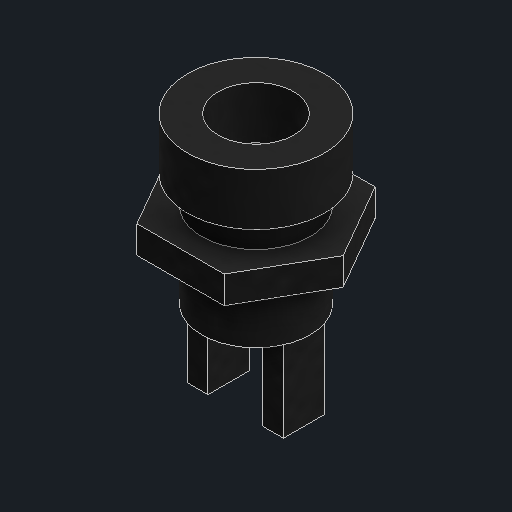
# Autodesk Inventor part: dc_socket_5.5x2.1_M8
Saved by Autodesk Inventor 2027.1 (Build 311270010, 270A)
## iProperties
Created: 2026-10-29
Part Number: dc_socket_5.5x2.1_M8
Material: Generic
Document SubType Name: Modeling
Designer: alexg
Density: 1 g/cm^3
Appearance: Black
Author: alexg
Autodesk Inventor part; units mm, degrees
sketch "Flange sketch" plane through (0, 0, 0) normal (0, 1, 0) x (-1, 0, 0)
  circle A0 centre (0, 0) radius 5
  constraints: 1 centre point
extrude "Flange" add sketch "Flange sketch" along normal blind 3.8
ref_plane "Work Plane1" through (0, 3.8, 0) normal (0, 1, 0) x (-1, 0, 0)
sketch "Barrel opening sketch" plane through (0, 3.8, 0) normal (0, 1, 0) x (-1, 0, 0)
  circle A0 centre (0, 0) radius 2.75
  constraints: 1 centre point
extrude "Barrel opening" cut sketch "Barrel opening sketch" against normal blind 3.8
sketch "Thread M8x1 sketch" plane through (0, 0, 0) normal (0, 1, 0) x (-1, 0, 0)
  circle A0 centre (0, 0) radius 3.95
  constraints: 1 centre point
extrude "Thread M8x1" add sketch "Thread M8x1 sketch" against normal blind 8.2
ref_plane "Work Plane2" through (0, -2, 0) normal (0, 1, 0) x (-1, 0, 0)
sketch "Nut sketch" plane through (0, -2, 0) normal (0, 1, 0) x (-1, 0, 0)
  line L0 (-6.3509, 0) -> (-3.1754, 5.5)
  line L1 (-3.1754, 5.5) -> (3.1754, 5.5)
  line L2 (3.1754, 5.5) -> (6.3509, 0)
  line L3 (6.3509, 0) -> (3.1754, -5.5)
  line L4 (3.1754, -5.5) -> (-3.1754, -5.5)
  line L5 (-3.1754, -5.5) -> (-6.3509, 0)
  constraints: 12 end point
extrude "Nut" add sketch "Nut sketch" against normal blind 2
ref_plane "Work Plane3" through (0, -8.2, 0) normal (0, 1, 0) x (-1, 0, 0)
sketch "Tabs sketch" plane through (0, -8.2, 0) normal (0, 1, 0) x (-1, 0, 0)
  line L0 (3.5, -1.5) -> (2, -1.5)
  line L1 (2, -1.5) -> (2, 1.5)
  line L2 (2, 1.5) -> (3.5, 1.5)
  line L3 (3.5, 1.5) -> (3.5, -1.5)
  line L4 (-2, -1.5) -> (-3.5, -1.5)
  line L5 (-3.5, -1.5) -> (-3.5, 1.5)
  line L6 (-3.5, 1.5) -> (-2, 1.5)
  line L7 (-2, 1.5) -> (-2, -1.5)
  constraints: 16 end point, 4 parallel, 2 horizontal, 2 perpendicular
extrude "Tabs" add sketch "Tabs sketch" against normal blind 6
body "Solid1"
